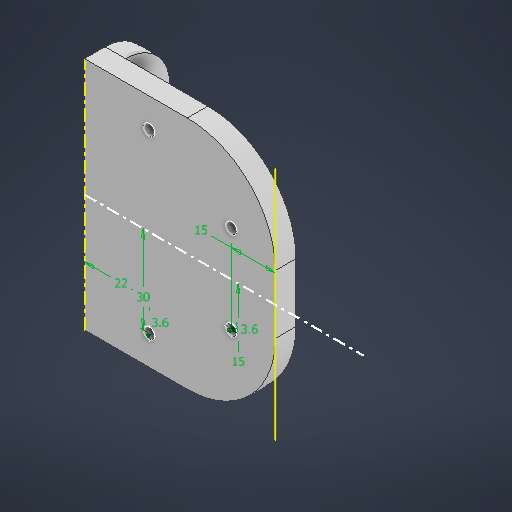
# Autodesk Inventor part: union_patas
Saved by Autodesk Inventor 2027 (Build 310192060, 192F)
## iProperties
Created: 2026-10-17
Part Number: union_patas
Material: Generic
Document SubType Name: Modeling
Designer: Pablo
Density: 1 g/cm^3
Appearance: Default
Author: Pablo
Autodesk Inventor part; units mm, degrees
ref_plane "YZ Plane" through (0, 0, 0) normal (1, 0, 0) x (0, 1, 0)
ref_plane "XZ Plane" through (0, 0, 0) normal (0, 1, 0) x (-1, 0, 0)
ref_plane "XY Plane" through (0, 0, 0) normal (0, 0, 1) x (1, 0, 0)
sketch "Sketch1" plane through (0, 0, 0) normal (0, 1, 0) x (-1, 0, 0)
  line L0 (0, 0) -> (0, -22)
  line L1 (0, -22) -> (-7, -22)
  line L2 (-7, -22) -> (-7, -7)
  line L3 (-7, -7) -> (-65, -7)
  line L4 (-65, -7) -> (-65, 0)
  line L5 (-65, 0) -> (0, 0)
  dimension "d1" = 7
  dimension "d3" = 7
  dimension "d17" = 58
  dimension "d18" = 15
  constraints: 12 end point, 5 perpendicular, 1 vertical
  measures "d1" distance of L0.end L1.end
  measures "d3" distance between parallel lines of L5 L3
  measures "d17" distance between parallel lines of L2 L4
  measures "d18" distance of L1.end L2.end
extrude "Extrusion1" add sketch "Sketch1" along normal blind 80
sketch "Sketch2" plane through (0, 0, 0) normal (0, 0, 1) x (1, 0, 0)
  line L0 (0, 0) -> (0, 80) projected
  line L1 (0, 40) -> (94.8076, 40)
  line L2 (65, 0) -> (65, 80) projected
  circle A0 centre (22, 10) radius 1.8
  circle A1 centre (50, 25) radius 1.8
  circle A2 centre (22, 70) radius 1.8
  circle A3 centre (50, 55) radius 1.8
  point P0 (22, 10)
  dimension "d7" = 15
  dimension "d8" = 30
  dimension "d9" = 15
  dimension "d10" = 22
  dimension "d12" = 3.6
  dimension "d13" = 3.6
  constraints: 4 centre point, 2 coincident, 2 end point, 2 symmetric about line, 1 horizontal, 1 midpoint, 2 other
  measures "d7" distance from line of point (50, 25) L1
  measures "d8" distance from line of point (22, 10) L1
  measures "d9" distance from line of L2 point (50, 25)
  measures "d10" distance from line of point (22, 10) L0
  measures "d12" diameter of A0
  measures "d13" diameter of A1
extrude "Extrusion2" cut sketch "Sketch2" against normal through all
sketch "Sketch3" plane through (0, 0, -22) normal (-1, 0, 0) x (0, 0, 1)
  line L0 (22, 0) -> (22, 80) projected
  line L1 (22, 40) -> (-16.0561, 40)
  circle A0 centre (7.5, 25) radius 1.8
  line L2 (15, 0) -> (15, 80) projected
  circle A1 centre (7.5, 55) radius 1.8
  dimension "d19" = 3.6
  dimension "d20" = 30
  dimension "d21" = 7.5
  constraints: 2 centre point, 2 end point, 1 horizontal, 1 midpoint, 1 symmetric about line, 1 other
  measures "d19" diameter of A0
  measures "d20" diameter of A0.centre L1
  measures "d21" distance from line of A0.centre L2
extrude "Extrusion3" cut sketch "Sketch3" against normal blind 10
fillet "Fillet1" radius 30 2 edges at (65, 80, -3.5) (65, 0, -3.5)
fillet "Fillet2" radius 15 2 edges at (3.5, 80, -22) (3.5, 0, -22)
body "Solid1"
